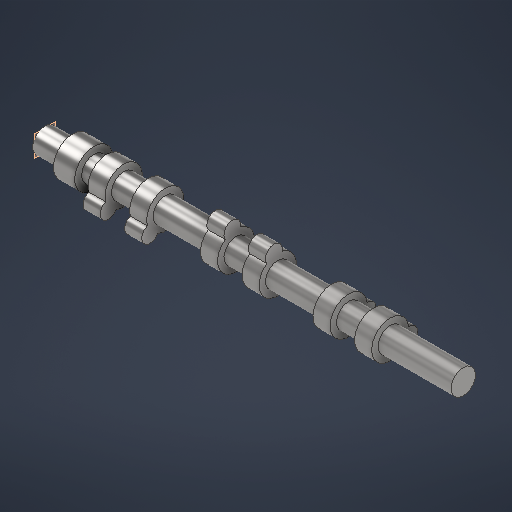
# Autodesk Inventor part: Camshaft_A_Exhaust
Saved by Autodesk Inventor 2027.1 (Build 311270010, 270A)
## iProperties
Created: 2026-10-17
Part Number: Camshaft_A_Exhaust
Material: Steel, Alloy
Document SubType Name: Modeling
Designer: kashyap
Density: 7.73 g/cm^3
Appearance: Semi-Polished
Mass: 1856.06 g
Surface Area: 444.793 cm^2
Volume: 240.112 cm^3
Material_Status: Assumed for this reconstruction
Author: kashyap
Autodesk Inventor part; units mm, degrees
derived "V6_Engine_Master.ipt"
ref_plane "Cam_Ref_Plane" through (0, 0, 0) normal (1, 0, 0) x (0, 1, 0)
ref_plane "Cam_Front_Plane" through (-209.25, 0, 0) normal (1, 0, 0) x (0, 1, 0)
sketch "SK_Shaft" plane through (-209.25, 0, 0) normal (1, 0, 0) x (0, 1, 0)
  circle A0 centre (0, 0) radius 11.5
  dimension "d21" = 23
  constraints: 1 centre point
  measures "d21" diameter of A0
extrude "Cam_Shaft" add sketch "SK_Shaft" along normal blind 392.5
ref_plane "Cam_Journal_1_Plane" through (-183.25, 0, 0) normal (1, 0, 0) x (0, 1, 0)
sketch "SK_Journal_1" plane through (-183.25, 0, 0) normal (1, 0, 0) x (0, 1, 0)
  circle A0 centre (0, 0) radius 18
  dimension "d25" = 36
  constraints: 1 centre point
  measures "d25" diameter of A0
extrude "Cam_Journal_1" add sketch "SK_Journal_1" along normal blind 20
ref_plane "Lobe_A1_F_Plane" through (-151.3, 0, 0) normal (1, 0, 0) x (0, 1, 0)
sketch "SK_Lobe_A1_F" plane through (-151.3, 0, 0) normal (1, 0, 0) x (0, 1, 0)
  circle A0 centre (0, 0) radius 17.5
  circle A1 centre (-12.3418, 14.1976) radius 8
  dimension "d29" = 35
  dimension "d30" = 18.812
  dimension "d31" = 16
  constraints: 2 centre point
  measures "d29" diameter of A0
  measures "d30" distance of point (0, 0) point (-12.342, 14.198)
  measures "d31" diameter of A1
extrude "Lobe_A1_F_VISUAL_REPRESENTATION" add sketch "SK_Lobe_A1_F" along normal blind 16
ref_plane "Lobe_A1_R_Plane" through (-112.3, 0, 0) normal (1, 0, 0) x (0, 1, 0)
sketch "SK_Lobe_A1_R" plane through (-112.3, 0, 0) normal (1, 0, 0) x (0, 1, 0)
  circle A0 centre (0, 0) radius 17.5
  circle A1 centre (-12.3418, 14.1976) radius 8
  dimension "d35" = 35
  dimension "d36" = 18.812
  dimension "d37" = 16
  constraints: 2 centre point
  measures "d35" diameter of A0
  measures "d36" distance of point (0, 0) point (-12.342, 14.198)
  measures "d37" diameter of A1
extrude "Lobe_A1_R_VISUAL_REPRESENTATION" add sketch "SK_Lobe_A1_R" along normal blind 16
ref_plane "Lobe_A2_F_Plane" through (-45.8, 0, 0) normal (1, 0, 0) x (0, 1, 0)
sketch "SK_Lobe_A2_F" plane through (-45.8, 0, 0) normal (1, 0, 0) x (0, 1, 0)
  circle A0 centre (0, 0) radius 17.5
  circle A1 centre (18.4664, 3.5895) radius 8
  dimension "d41" = 35
  dimension "d42" = 18.812
  dimension "d43" = 16
  constraints: 2 centre point
  measures "d41" diameter of A0
  measures "d42" distance of point (0, 0) point (18.466, 3.589)
  measures "d43" diameter of A1
extrude "Lobe_A2_F_VISUAL_REPRESENTATION" add sketch "SK_Lobe_A2_F" along normal blind 16
ref_plane "Lobe_A2_R_Plane" through (-6.8, 0, 0) normal (1, 0, 0) x (0, 1, 0)
sketch "SK_Lobe_A2_R" plane through (-6.8, 0, 0) normal (1, 0, 0) x (0, 1, 0)
  circle A0 centre (0, 0) radius 17.5
  circle A1 centre (18.4664, 3.5895) radius 8
  dimension "d47" = 35
  dimension "d48" = 18.812
  dimension "d49" = 16
  constraints: 2 centre point
  measures "d47" diameter of A0
  measures "d48" distance of point (0, 0) point (18.466, 3.589)
  measures "d49" diameter of A1
extrude "Lobe_A2_R_VISUAL_REPRESENTATION" add sketch "SK_Lobe_A2_R" along normal blind 16
ref_plane "Lobe_A3_F_Plane" through (59.7, 0, 0) normal (1, 0, 0) x (0, 1, 0)
sketch "SK_Lobe_A3_F" plane through (59.7, 0, 0) normal (1, 0, 0) x (0, 1, 0)
  circle A0 centre (0, 0) radius 17.5
  circle A1 centre (-6.1246, -17.7871) radius 8
  dimension "d53" = 35
  dimension "d54" = 18.812
  dimension "d55" = 16
  constraints: 2 centre point
  measures "d53" diameter of A0
  measures "d54" distance of point (0, 0) point (-6.125, -17.787)
  measures "d55" diameter of A1
extrude "Lobe_A3_F_VISUAL_REPRESENTATION" add sketch "SK_Lobe_A3_F" along normal blind 16
ref_plane "Lobe_A3_R_Plane" through (98.7, 0, 0) normal (1, 0, 0) x (0, 1, 0)
sketch "SK_Lobe_A3_R" plane through (98.7, 0, 0) normal (1, 0, 0) x (0, 1, 0)
  circle A0 centre (0, 0) radius 17.5
  circle A1 centre (-6.1246, -17.7871) radius 8
  dimension "d59" = 35
  dimension "d60" = 18.812
  dimension "d61" = 16
  constraints: 2 centre point
  measures "d59" diameter of A0
  measures "d60" distance of point (0, 0) point (-6.125, -17.787)
  measures "d61" diameter of A1
extrude "Lobe_A3_R_VISUAL_REPRESENTATION" add sketch "SK_Lobe_A3_R" along normal blind 16
equation "\"d21\" = Cam_Journal_Dia_Other"
equation "\"d25\" = Cam_Journal_Dia_No1"
equation "\"d29\" = Cam_Base_Circle_Dia"
equation "\"d30\" = -0.5 * Cam_Base_Circle_Dia + Exhaust_Cam_Lobe_Height - 0.5 * Cam_Nose_Dia"
equation "\"d31\" = Cam_Nose_Dia"
equation "\"d32\" = Cam_Lobe_Width"
equation "\"d35\" = Cam_Base_Circle_Dia"
equation "\"d36\" = -0.5 * Cam_Base_Circle_Dia + Exhaust_Cam_Lobe_Height - 0.5 * Cam_Nose_Dia"
equation "\"d37\" = Cam_Nose_Dia"
equation "\"d38\" = Cam_Lobe_Width"
equation "\"d41\" = Cam_Base_Circle_Dia"
equation "\"d42\" = -0.5 * Cam_Base_Circle_Dia + Exhaust_Cam_Lobe_Height - 0.5 * Cam_Nose_Dia"
equation "\"d43\" = Cam_Nose_Dia"
equation "\"d44\" = Cam_Lobe_Width"
equation "\"d47\" = Cam_Base_Circle_Dia"
equation "\"d48\" = -0.5 * Cam_Base_Circle_Dia + Exhaust_Cam_Lobe_Height - 0.5 * Cam_Nose_Dia"
equation "\"d49\" = Cam_Nose_Dia"
equation "\"d50\" = Cam_Lobe_Width"
equation "\"d53\" = Cam_Base_Circle_Dia"
equation "\"d54\" = -0.5 * Cam_Base_Circle_Dia + Exhaust_Cam_Lobe_Height - 0.5 * Cam_Nose_Dia"
equation "\"d55\" = Cam_Nose_Dia"
equation "\"d56\" = Cam_Lobe_Width"
equation "\"d59\" = Cam_Base_Circle_Dia"
equation "\"d60\" = -0.5 * Cam_Base_Circle_Dia + Exhaust_Cam_Lobe_Height - 0.5 * Cam_Nose_Dia"
equation "\"d61\" = Cam_Nose_Dia"
equation "\"d62\" = Cam_Lobe_Width"
equation "\"Cam_Journal_Dia_Other\" = 23"
equation "\"Cam_Journal_Dia_No1\" = 36"
equation "\"Cam_Base_Circle_Dia\" = 35"
equation "\"Cam_Nose_Dia\" = 16"
equation "\"Cam_Lobe_Width\" = 16"
equation "\"Exhaust_Cam_Lobe_Height\" = 44.312"
body "Solid1"
